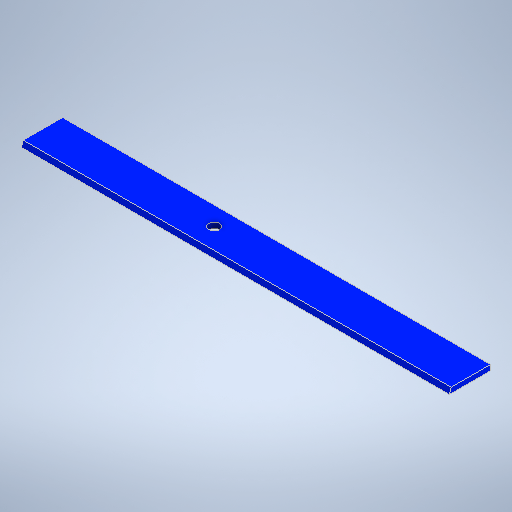
# Autodesk Inventor part: Higher_Section_Plate
Saved by Autodesk Inventor 2026.2 (Build 302298000, 298)
## iProperties
Created: 2026-07-14
Part Number: Higher_Section_Plate
Material: M-Foam PVC foam
Document SubType Name: Modeling
Designer: Taiye Raji
Density: 0.13 g/cm^3
Appearance: Generic
Mass: 596.258 g
Surface Area: 5313.15 cm^2
Volume: 4586.6 cm^3
Author: Taiye Raji
Autodesk Inventor part; units mm, degrees
ref_plane "YZ Plane" through (0, 0, 0) normal (1, 0, 0) x (0, 1, 0)
ref_plane "XZ Plane" through (0, 0, 0) normal (0, 1, 0) x (-1, 0, 0)
ref_plane "XY Plane" through (0, 0, 0) normal (0, 0, 1) x (1, 0, 0)
sketch "Sketch1" plane through (0, 0, 0) normal (0, 1, 0) x (-1, 0, 0)
  line L0 (-783, 75.7572) -> (783, 75.7572)
  line L1 (783, 75.7572) -> (783, -75.7572)
  line L2 (783, -75.7572) -> (-783, -75.7572)
  line L3 (-783, -75.7572) -> (-783, 75.7572)
  line L4 (-783, 75.7572) -> (783, -75.7572) construction
  line L5 (783, 75.7572) -> (-783, -75.7572) construction
  circle A0 centre (160, -6.3378) radius 20
  point P0 (0, 0)
  dimension "d0" = 1566
  dimension "d1" = 151.5145
  dimension "d11" = 40
  dimension "d12" = 160
  dimension "d13" = 82.095
  constraints: 12 end point, 2 midpoint, 2 parallel, 1 centre point, 1 horizontal, 1 perpendicular
  measures "d0" distance of L1.end L2.end
  measures "d1" distance of L2.end L0.start
  measures "d11" diameter of A0
  measures "d12" horizontal distance of A0.centre point (0, 0)
  measures "d13" distance from line of L0 A0.centre
extrude "Extrusion1" add sketch "Sketch1" along normal blind 20
sketch "Sketch2" plane through (783, 0, 75.7572) normal (1, 0, 0) x (0, 0, -1)
  line L0 (0, 0) -> (6.4984, 20)
  line L1 (151.5144, 20) -> (0, 20) projected
  line L2 (6.4984, 20) -> (151.5144, 20)
  line L3 (151.5144, 0) -> (151.5144, 20) projected
  line L4 (151.5144, 20) -> (151.5144, 0)
  line L5 (151.5144, 0) -> (0, 0)
  line L6 (0, 0) -> (0, 20)
  point P0 (75.7572, 0)
  point P1 (6.4984, 20)
  point P2 (0, 21)
  dimension "d21" = 72
  constraints: 10 end point, 2 perpendicular, 1 collinear, 1 vertical
  measures "d21" angle of L5 L0
extrude "Extrusion2" cut sketch "Sketch2" against normal blind 1566 contours L6 L1 L0
move faces "Move1" translate (0, 0, 0.832) faces at (261, 6.6667, -75.7572)
move faces "Move2" translate (0, 0, 0.1875) faces at (261, 6.6667, -74.9252)
body "Solid1"
